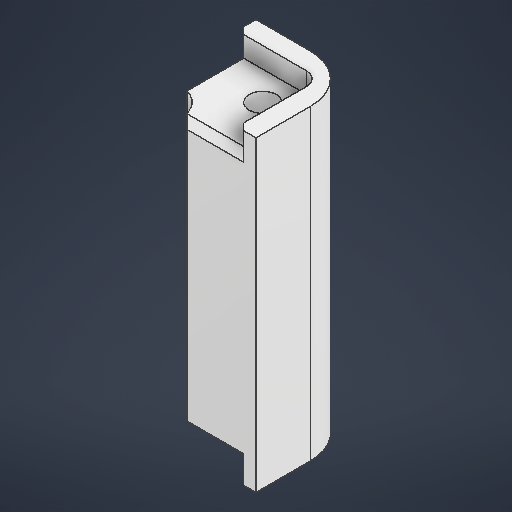
# Autodesk Inventor part: Pillar
Saved by Autodesk Inventor 2026.2 (Build 302298010, 298A)
## iProperties
Created: 2026-04-29
Part Number: Pillar
Material: ABS 플라스틱
Document SubType Name: Modeling
Designer: work
Density: 1.06 g/cm^3
Appearance: 매끄러움 - 흰색
Author: work
Autodesk Inventor part; units mm, degrees
ref_plane "YZ Plane" through (0, 0, 0) normal (1, 0, 0) x (0, 1, 0)
ref_plane "XZ Plane" through (0, 0, 0) normal (0, 1, 0) x (-1, 0, 0)
sketch "스케치1" plane through (0, 0, 0) normal (0, 1, 0) x (-1, 0, 0)
  circle A0 centre (0, 0) radius 2
  line L0 (0, 0) -> (8, 0) construction
  line L1 (0, 0) -> (0, 8) construction
  line L2 (8, 4) -> (8, -7)
  line L3 (8, -7) -> (0, -7)
  line L4 (8, 4) -> (4, 4)
  line L5 (4, 4) -> (4, 8)
  line L6 (4, 8) -> (-7, 8)
  line L7 (-7, 8) -> (-7, 0)
  arc A1 (-7, 0) -> (0, -7) centre (0, 0) ccw
  line L8 (0, 0) -> (-7, 0) construction
  line L9 (0, 0) -> (0, -7) construction
  dimension "d0" = 4
  dimension "d9" = 4
  dimension "d10" = 4
  dimension "d20" = 7
  dimension "d21" = 8
  dimension "d22" = 8
  constraints: 20 end point, 3 perpendicular, 2 centre point, 2 horizontal, 2 point on circle, 2 point on line, 2 vertical, 1 coincident, 1 collinear, 1 concentric, 1 parallel, 1 tangent
  measures "d0" diameter of A0
  measures "d9" distance of L4.end L5.end
  measures "d10" distance of L2.start L4.end
  measures "d20" distance of L3.end point (0, 0)
  measures "d21" distance of L1.end point (0, 0)
  measures "d22" distance of L0.end point (0, 0)
extrude "돌출1" add sketch "스케치1" along normal blind 45
sketch "스케치2" plane through (0, 45, 0) normal (0, 1, 0) x (1, 0, 0)
  line L0 (-4, -8) -> (7, -8) projected
  line L1 (7, -8) -> (7, 0) projected
  arc A0 (7, 0) -> (0, 7) centre (0, 0) ccw projected
  line L2 (0, 7) -> (-8, 7) projected
  line L3 (-8, 7) -> (-8, -4) projected
  line L4 (-8, -4) -> (-4, -4) projected
  line L5 (-4, -4) -> (-4, -8) projected
  circle A1 centre (0, 0) radius 2 projected
  line L6 (4.2, 2.2) -> (4.2, -8)
  line L7 (3.1813, 4.2) -> (-8, 4.2)
  circle A2 centre (2.2, 2.2) radius 2
  point P0 (2.2, 4.2)
  dimension "d23" = 4
  dimension "d24" = 2.8
  dimension "d25" = 2.8
  constraints: 4 end point, 2 horizontal, 2 point on line, 1 perpendicular, 1 vertical, 3 other
  measures "d24" distance between parallel lines of L1 L6
  measures "d25" distance from line of L2.start L7
extrude "돌출2" cut sketch "스케치2" against normal blind 3 contours L5 L4 L3 L7 A2 A1 L6 L0 | A2 A1 picked at (2.875, 2.875)
ref_plane "작업 평면1" through (0, 22.5, 0) normal (0, 1, 0) x (1, 0, 0)
mirror "미러1" about plane through (0, 22.5, 0) normal (0, 1, 0) of "돌출2"
fillet "모깎기1" radius 4 1 edges at (-4, 22.5, 4)
chamfer "모따기1" distance 1 angle 45 12 edges at (-4, 22.5, 7.9995) (-4, 22.5, 8) (0.1, 42, 8) (4.2, 43.5, 8) (0.1, 3, 8) (4.2, 1.5, 8) (-8, 3, -0.1) (-8, 42, -0.1) (-7.9995, 22.5, 4) (-8, 22.5, 4) (-8, 43.5, -4.2) (-8, 1.5, -4.2)
